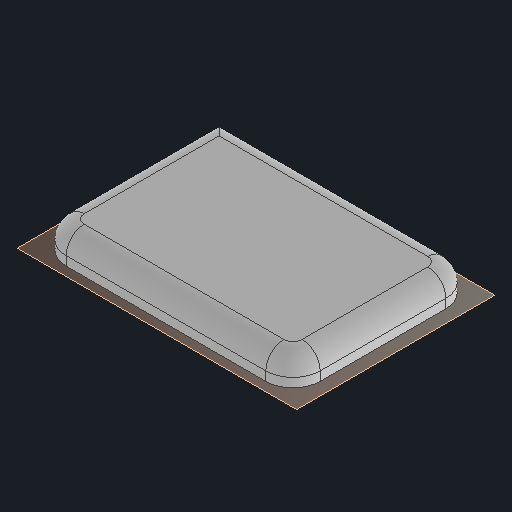
# Autodesk Inventor part: case4
Saved by Autodesk Inventor 2026.2 (Build 302298000, 298)
## iProperties
Created: 2026-10-14
Part Number: case4
Material: Generisch
Document SubType Name: Modeling
Designer: leo
Density: 1 g/cm^3
Appearance: Vorgabe
Author: leo
Autodesk Inventor part; units mm, degrees
ref_plane "YZ Plane" through (0, 0, 0) normal (1, 0, 0) x (0, 1, 0)
ref_plane "XZ Plane" through (0, 0, 0) normal (0, 1, 0) x (-1, 0, 0)
ref_plane "XY Plane" through (0, 0, 0) normal (0, 0, 1) x (1, 0, 0)
ref_plane "Arbeitsebene1" through (0, 0, 0) normal (0, 0, 1) x (1, 0, 0)
sketch "Skizze1" plane through (0, 0, 0) normal (0, 0, 1) x (1, 0, 0)
  arc A0 (-14, -6.925) -> (-11, -9.925) centre (-11, -6.925) ccw projected
  line L0 (-11, -9.925) -> (11, -9.925) projected
  arc A1 (11, -9.925) -> (14, -6.925) centre (11, -6.925) ccw projected
  line L1 (14, -6.925) -> (14, 6.925) projected
  arc A2 (14, 6.925) -> (11, 9.925) centre (11, 6.925) ccw projected
  line L2 (11, 9.925) -> (-14, 9.925) projected
  line L3 (-14, 9.925) -> (-14, -6.925) projected
  line L4 (-11, 5.3526) -> (9, 5.3526) projected
  line L5 (9, 5.3526) -> (9, -7.6474) projected
  line L6 (9, -7.6474) -> (-11, -7.6474) projected
  line L7 (-11, -7.6474) -> (-11, 5.3526) projected
  point P0 (0, 0)
extrude "Extrusion1" add sketch "Skizze1" along normal blind 3 contours L3 L2 A2 L1 A1 L0 A0 | L4 L5 L6 L7
fillet "Rundung1" radius 2 7 edges at (-13.1213, -9.0463, 3) (0, -9.925, 3) (13.1213, -9.0463, 3) (14, 0, 3) (13.1213, 9.0463, 3) (-1.5, 9.925, 3) (-14, 1.5, 3)
